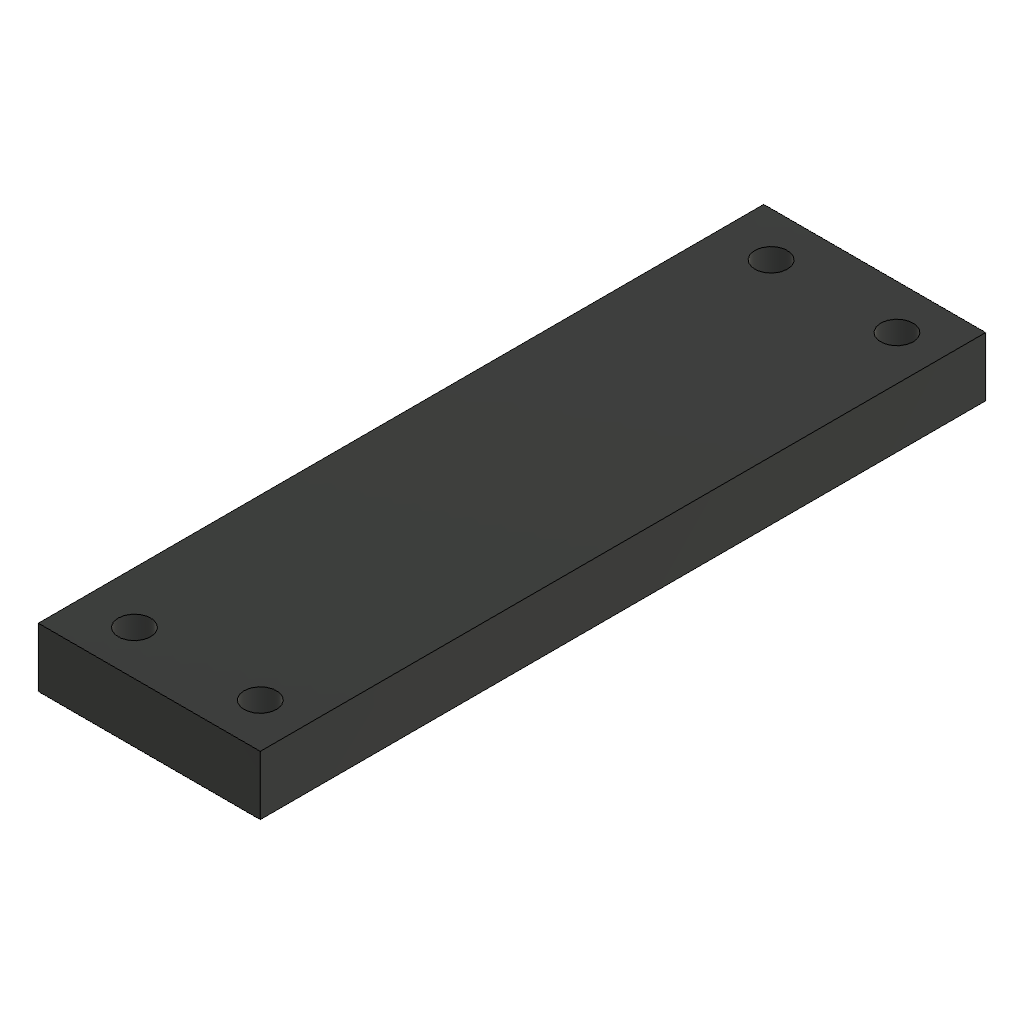
root_cap (Autodesk Fusion 360 design; units mm, degrees)
part number: 2026-10-10-16-37-39-079
Autodesk Fusion 360 part; units mm, degrees
sketch "Upper root jaw sketch" plane through (0, 0, 0) normal (0, 0, 1) x (1, 0, 0)
  line L0 (-4, -49) -> (26, -49)
  line L1 (26, -49) -> (26, 49)
  line L2 (26, 49) -> (-4, 49)
  line L3 (-4, 49) -> (-4, -49)
extrude "Upper root jaw" add sketch "Upper root jaw sketch" along normal blind 8
ref_plane "WorkPlane1" through (0, 0, -0.05) normal (0, 0, 1) x (1, 0, 0)
sketch "Cap bolt 3 -43 sketch" plane through (0, 0, -0.05) normal (0, 0, 1) x (1, 0, 0)
  circle A0 centre (3, -43) radius 2.2
  dimension "d219" = 4.4
  measures "d219" diameter of A0
extrude "Cap bolt 3 -43" cut sketch "Cap bolt 3 -43 sketch" along normal blind 8.1
ref_plane "WorkPlane2" through (0, 0, -0.05) normal (0, 0, 1) x (1, 0, 0)
sketch "Cap bolt 3 43 sketch" plane through (0, 0, -0.05) normal (0, 0, 1) x (1, 0, 0)
  circle A0 centre (3, 43) radius 2.2
  dimension "d224" = 4.4
  measures "d224" diameter of A0
extrude "Cap bolt 3 43" cut sketch "Cap bolt 3 43 sketch" along normal blind 8.1
ref_plane "WorkPlane3" through (0, 0, -0.05) normal (0, 0, 1) x (1, 0, 0)
sketch "Cap bolt 20 -43 sketch" plane through (0, 0, -0.05) normal (0, 0, 1) x (1, 0, 0)
  circle A0 centre (20, -43) radius 2.2
  dimension "d229" = 4.4
  measures "d229" diameter of A0
extrude "Cap bolt 20 -43" cut sketch "Cap bolt 20 -43 sketch" along normal blind 8.1
ref_plane "WorkPlane4" through (0, 0, -0.05) normal (0, 0, 1) x (1, 0, 0)
sketch "Cap bolt 20 43 sketch" plane through (0, 0, -0.05) normal (0, 0, 1) x (1, 0, 0)
  circle A0 centre (20, 43) radius 2.2
  dimension "d234" = 4.4
  measures "d234" diameter of A0
extrude "Cap bolt 20 43" cut sketch "Cap bolt 20 43 sketch" along normal blind 8.1
equation "d219 = m4Clearance"
equation "d224 = m4Clearance"
equation "d229 = m4Clearance"
equation "d234 = m4Clearance"
equation "m4Clearance = 4.4 mm" comment "Root clamp bolt holes"
named bodies: "root_cap - printable solid"
